Autodesk Fusion 360 part; units mm, degrees
(part 3 of 3)
  spline S17 degree 5 poles (11.8031, 8.4131) (11.801, 8.4065) (11.7969, 8.3933) (11.7907, 8.3736) (11.7826, 8.3472) (11.7727, 8.3143) (11.763, 8.2814) (11.7535, 8.2485) (11.7443, 8.2156) (11.7353, 8.1828) (11.7265, 8.1499) (11.718, 8.1171) (11.7097, 8.0843) (11.7017, 8.0515) (11.6938, 8.0188) (11.6862, 7.986) (11.6789, 7.9533) (11.6718, 7.9206) (11.6649, 7.888) (11.6582, 7.8554) (11.6518, 7.8228) (11.6457, 7.7902) (11.6398, 7.7577) (11.6341, 7.7253) (11.6287, 7.6928) (11.6235, 7.6604) (11.6186, 7.6281) (11.6139, 7.5958) (11.6094, 7.5635) (11.6053, 7.5313) (11.6013, 7.4991) (11.5977, 7.467) (11.5942, 7.4349) (11.5911, 7.4029) (11.5882, 7.371) (11.5855, 7.3391) (11.5831, 7.3073) (11.581, 7.2755) (11.5792, 7.2438) (11.5776, 7.2122) (11.5762, 7.1806) (11.5752, 7.1491) (11.5744, 7.1177) (11.574, 7.0864) (11.5738, 7.0551) (11.5738, 7.024) (11.5742, 6.9929) (11.5748, 6.9619) (11.5758, 6.931) (11.577, 6.9002) (11.5785, 6.8695) (11.5804, 6.8389) (11.5825, 6.8084) (11.585, 6.778) (11.5879, 6.7477) (11.591, 6.7176) (11.5945, 6.6876) (11.5982, 6.6576) (11.6022, 6.6278) (11.6066, 6.5981) (11.6114, 6.5686) (11.6167, 6.5393) (11.6225, 6.5102) (11.6287, 6.4813) (11.6355, 6.4526) (11.6425, 6.424) (11.6498, 6.3955) (11.6574, 6.3672) (11.6652, 6.339) (11.6737, 6.3112) (11.6832, 6.2838) (11.6919, 6.2623) (11.6992, 6.2466) (11.7045, 6.2363) (11.7072, 6.2312) knots -1 -1 -1 -1 -1 -1 -0.98571429 -0.97142857 -0.95714286 -0.94285714 -0.92857143 -0.91428571 -0.9 -0.88571429 -0.87142857 -0.85714286 -0.84285714 -0.82857143 -0.81428571 -0.8 -0.78571429 -0.77142857 -0.75714286 -0.74285714 -0.72857143 -0.71428571 -0.7 -0.68571429 -0.67142857 -0.65714286 -0.64285714 -0.62857143 -0.61428571 -0.6 -0.58571429 -0.57142857 -0.55714286 -0.54285714 -0.52857143 -0.51428571 -0.5 -0.48571429 -0.47142857 -0.45714286 -0.44285714 -0.42857143 -0.41428571 -0.4 -0.38571429 -0.37142857 -0.35714286 -0.34285714 -0.32857143 -0.31428571 -0.3 -0.28571429 -0.27142857 -0.25714286 -0.24285714 -0.22857143 -0.21428571 -0.2 -0.18571429 -0.17142857 -0.15714286 -0.14285714 -0.12857143 -0.11428571 -0.1 -0.08571429 -0.07142857 -0.05714286 -0.04285714 -0.02857143 -0.01428571 0 0 0 0 0 0
  line L17 (11.7072, 6.2312) -> (12.2604, 5.1843)
  arc A35 (12.2202, 5.05) -> (12.2604, 5.1843) centre (12.172, 5.1376) ccw
  arc A36 (12.2202, 5.05) -> (11.0562, 4.2043) centre (15, 0) ccw
  arc A37 (10.916, 4.2076) -> (11.0562, 4.2043) centre (10.9878, 4.2772) ccw
  line L18 (10.916, 4.2076) -> (10.0914, 5.0572)
  spline S18 degree 5 poles (10.0914, 5.0572) (10.0873, 5.0613) (10.0791, 5.0695) (10.0664, 5.0813) (10.0487, 5.0962) (10.0256, 5.1137) (10.0017, 5.1304) (9.9774, 5.1466) (9.9527, 5.1625) (9.9279, 5.1783) (9.903, 5.1938) (9.8777, 5.2091) (9.8522, 5.224) (9.8263, 5.2385) (9.8, 5.2525) (9.7734, 5.2662) (9.7465, 5.2796) (9.7194, 5.2926) (9.6921, 5.3054) (9.6646, 5.318) (9.6369, 5.3303) (9.609, 5.3423) (9.5809, 5.3541) (9.5526, 5.3656) (9.524, 5.3768) (9.4953, 5.3878) (9.4664, 5.3984) (9.4373, 5.4089) (9.408, 5.4191) (9.3785, 5.429) (9.3489, 5.4387) (9.3191, 5.4482) (9.2892, 5.4574) (9.2591, 5.4664) (9.2288, 5.4751) (9.1984, 5.4836) (9.1678, 5.4919) (9.1371, 5.4999) (9.1062, 5.5077) (9.0752, 5.5153) (9.0441, 5.5226) (9.0128, 5.5297) (8.9814, 5.5366) (8.9499, 5.5433) (8.9182, 5.5497) (8.8864, 5.5559) (8.8544, 5.5619) (8.8224, 5.5676) (8.7902, 5.5731) (8.7579, 5.5784) (8.7255, 5.5835) (8.693, 5.5884) (8.6603, 5.593) (8.6276, 5.5975) (8.5947, 5.6017) (8.5617, 5.6056) (8.5287, 5.6094) (8.4955, 5.613) (8.4622, 5.6163) (8.4288, 5.6194) (8.3954, 5.6223) (8.3618, 5.625) (8.3281, 5.6274) (8.2944, 5.6297) (8.2605, 5.6317) (8.2266, 5.6335) (8.1925, 5.6351) (8.1584, 5.6365) (8.1242, 5.6377) (8.0899, 5.6386) (8.0556, 5.6394) (8.028, 5.6398) (8.0073, 5.64) (7.9935, 5.6401) (7.9866, 5.6402) knots 0 0 0 0 0 0 0.01428571 0.02857143 0.04285714 0.05714286 0.07142857 0.08571429 0.1 0.11428571 0.12857143 0.14285714 0.15714286 0.17142857 0.18571429 0.2 0.21428571 0.22857143 0.24285714 0.25714286 0.27142857 0.28571429 0.3 0.31428571 0.32857143 0.34285714 0.35714286 0.37142857 0.38571429 0.4 0.41428571 0.42857143 0.44285714 0.45714286 0.47142857 0.48571429 0.5 0.51428571 0.52857143 0.54285714 0.55714286 0.57142857 0.58571429 0.6 0.61428571 0.62857143 0.64285714 0.65714286 0.67142857 0.68571429 0.7 0.71428571 0.72857143 0.74285714 0.75714286 0.77142857 0.78571429 0.8 0.81428571 0.82857143 0.84285714 0.85714286 0.87142857 0.88571429 0.9 0.91428571 0.92857143 0.94285714 0.95714286 0.97142857 0.98571429 1 1 1 1 1 1
  arc A38 (7.9866, 5.6402) -> (7.4686, 4.9273) centre (15, 0) ccw
  spline S19 degree 5 poles (7.4686, 4.9273) (7.4708, 4.9207) (7.4751, 4.9076) (7.4818, 4.888) (7.4907, 4.8619) (7.502, 4.8294) (7.5135, 4.7971) (7.5252, 4.765) (7.5371, 4.7329) (7.5491, 4.7011) (7.5613, 4.6693) (7.5737, 4.6378) (7.5863, 4.6064) (7.599, 4.5751) (7.6119, 4.544) (7.625, 4.5131) (7.6383, 4.4823) (7.6518, 4.4516) (7.6654, 4.4212) (7.6792, 4.3909) (7.6932, 4.3608) (7.7073, 4.3308) (7.7216, 4.301) (7.7361, 4.2714) (7.7508, 4.242) (7.7657, 4.2127) (7.7807, 4.1837) (7.7959, 4.1548) (7.8113, 4.1261) (7.8268, 4.0976) (7.8426, 4.0692) (7.8585, 4.0411) (7.8745, 4.0131) (7.8908, 3.9854) (7.9072, 3.9578) (7.9238, 3.9305) (7.9406, 3.9033) (7.9575, 3.8764) (7.9747, 3.8496) (7.992, 3.8231) (8.0095, 3.7968) (8.0271, 3.7707) (8.045, 3.7449) (8.063, 3.7192) (8.0812, 3.6938) (8.0996, 3.6687) (8.1181, 3.6437) (8.1369, 3.619) (8.1558, 3.5946) (8.1749, 3.5704) (8.1942, 3.5464) (8.2137, 3.5227) (8.2333, 3.4993) (8.2532, 3.4763) (8.2733, 3.4534) (8.2936, 3.4309) (8.314, 3.4086) (8.3346, 3.3866) (8.3554, 3.3649) (8.3764, 3.3434) (8.3976, 3.3224) (8.4191, 3.3017) (8.4409, 3.2816) (8.463, 3.2619) (8.4853, 3.2426) (8.5078, 3.2236) (8.5305, 3.2049) (8.5532, 3.1864) (8.5761, 3.1683) (8.5994, 3.1507) (8.6232, 3.1341) (8.6428, 3.1219) (8.658, 3.1135) (8.6683, 3.1082) (8.6735, 3.1056) knots -1 -1 -1 -1 -1 -1 -0.98571429 -0.97142857 -0.95714286 -0.94285714 -0.92857143 -0.91428571 -0.9 -0.88571429 -0.87142857 -0.85714286 -0.84285714 -0.82857143 -0.81428571 -0.8 -0.78571429 -0.77142857 -0.75714286 -0.74285714 -0.72857143 -0.71428571 -0.7 -0.68571429 -0.67142857 -0.65714286 -0.64285714 -0.62857143 -0.61428571 -0.6 -0.58571429 -0.57142857 -0.55714286 -0.54285714 -0.52857143 -0.51428571 -0.5 -0.48571429 -0.47142857 -0.45714286 -0.44285714 -0.42857143 -0.41428571 -0.4 -0.38571429 -0.37142857 -0.35714286 -0.34285714 -0.32857143 -0.31428571 -0.3 -0.28571429 -0.27142857 -0.25714286 -0.24285714 -0.22857143 -0.21428571 -0.2 -0.18571429 -0.17142857 -0.15714286 -0.14285714 -0.12857143 -0.11428571 -0.1 -0.08571429 -0.07142857 -0.05714286 -0.04285714 -0.02857143 -0.01428571 0 0 0 0 0 0
  line L19 (8.6735, 3.1056) -> (9.7364, 2.5839)
  arc A39 (9.7828, 2.4516) -> (9.7364, 2.5839) centre (9.6923, 2.4941) ccw
  circle A40 centre (15, 0) radius 2.35
  circle A41 centre (15, 0) radius 2.35
  circle A42 centre (15, 0) radius 1.4
  dimension "d56" = 2.8
  constraint concentric A0 A41
  constraint concentric A41 A42
  measures "d56" diameter of A42
extrude "Extrude12" add sketch "Sketch15" against normal blind 2 contours A40 A41 bodies 4 5
extrude "Extrude13" cut 1 faces at (-15.325, 3.7601, 3) along direction (0, 0, -1) blind 1 on bodies 4 bodies 4
extrude "Extrude14" cut 1 faces at (15.325, 3.7601, 3) along direction (0, 0, -1) blind 1 on bodies 3 bodies 3
sketch "Sketch16" plane through (45, 0, 0) normal (-1, 0, 0) x (0, -1, 0)
  line L0 (-10, 0) -> (-10, 5)
  line L1 (-10, 5) -> (-110, 5)
  line L2 (-110, 5) -> (-110, 0)
  line L3 (-110, 0) -> (-10, 0)
  line L4 (-10, 5) -> (-60, 5)
  line L5 (-60, 5) -> (-60, 0)
  line L6 (-60, 0) -> (-52, 0)
  line L7 (-52, 0) -> (-52, 5)
  dimension "d63" = 50
  dimension "d64" = 8
  dimension "d65" = 5
  constraint coincident L0.end L1.start
  constraint perpendicular L2 L4
  constraint midpoint L3 L5.end
  constraint perpendicular L5 L6
  measures "d63" distance of L0.end L4.end
  measures "d64" distance of L5.end L6.end
  measures "d65" distance of L6.end L7.end
sketch "Sketch17" plane through (-45, 0, 0) normal (1, 0, 0) x (0, 1, 0)
  line L0 (10, 5) -> (10, 0)
  line L1 (10, 0) -> (110, 0)
  line L2 (110, 0) -> (110, 5)
  line L3 (110, 5) -> (10, 5)
  line L4 (10, 5) -> (60, 5)
  line L5 (60, 5) -> (60, 0)
  line L6 (60, 0) -> (52, 0)
  line L7 (52, 0) -> (52, 5)
  dimension "d66" = 50
  dimension "d67" = 8
  constraint coincident L0.start L3.end
  constraint perpendicular L0 L4
  constraint midpoint L1 L5.end
  constraint perpendicular L5 L6
  constraint coincident L4 L7.end
  measures "d66" distance of L0.start L4.end
  measures "d67" distance of L5.end L6.end
extrude "Extrude15" add sketch "Sketch17" along normal blind 25 contours L1 L3 L4 L5 L6 L7 bodies 4
extrude "Extrude16" add sketch "Sketch16" along normal blind 25 contours L1 L3 L4 L5 L6 L7 bodies 3
equation "d31 = ( 8.5 * 2 ) * 1 mm"
named bodies: "right gear", "right claw", "Spur Gear (10 teeth)", "left gear", "left claw"
